Autodesk Fusion 360 part; units mm, degrees
(part 6 of 10)
sketch "Thin nut envelope sketch (13)" plane through (0, 0, 20.6) normal (0, 0, 1) x (1, 0, 0) in component "REFERENCE thin METAL channel nut side 00R Y"
  line L0 (92, 17.8) -> (104, 17.8)
  line L1 (104, 17.8) -> (104, 20.5)
  line L2 (104, 20.5) -> (92, 20.5)
  line L3 (92, 20.5) -> (92, 17.8)
  dimension "d2381" = 92
  dimension "d2382" = 17.8
  dimension "d2383" = 12
  dimension "d2384" = 2.7
  constraint horizontal L0
  constraint vertical L1
  constraint horizontal L2
  constraint vertical L3
  measures "d2381" horizontal distance of origin L0.start
  measures "d2382" vertical distance of origin L0.start
  measures "d2383" horizontal distance of L0.start L0.end
  measures "d2384" vertical distance of L0.end L1.end
extrude "Thin nut envelope''''''''''''" add sketch "Thin nut envelope sketch (13)" along normal blind 8.8 separate body makes body 66 in component "REFERENCE thin METAL channel nut side 00R Y"
ref_plane "WorkPlane2" through (0, 17.8, 0) normal (0, 1, 0) x (0, 0, 1) in component "REFERENCE thin METAL channel nut side 00R Y"
sketch "Thread envelope sketch (13)" plane through (0, 17.8, 0) normal (0, 1, 0) x (1, 0, 0) in component "REFERENCE thin METAL channel nut side 00R Y"
  circle A0 centre (98, -25) radius 2.6
  dimension "d2389" = 98
  dimension "d2390" = 25
  dimension "d2391" = 5.2
  measures "d2389" horizontal distance of origin A0.centre
  measures "d2390" vertical distance of origin A0.centre
  measures "d2391" diameter of A0
extrude "Thread envelope''''''''''''" cut sketch "Thread envelope sketch (13)" along normal blind 2.7 bodies 66 in component "REFERENCE thin METAL channel nut side 00R Y"
ref_plane "WorkPlane1" through (0, 0, 17) normal (0, 0, 1) x (1, 0, 0) in component "METAL in-bay corner 10L"
sketch "Vertical bracket leg sketch (3)" plane through (0, 0, 17) normal (0, 0, 1) x (1, 0, 0) in component "METAL in-bay corner 10L"
  line L0 (130, 22) -> (133, 22)
  line L1 (133, 22) -> (133, 40)
  line L2 (133, 40) -> (130, 40)
  line L3 (130, 40) -> (130, 22)
  dimension "d2396" = 130
  dimension "d2397" = 22
  dimension "d2398" = 3
  dimension "d2399" = 18
  constraint horizontal L0
  constraint vertical L1
  constraint horizontal L2
  constraint vertical L3
  measures "d2396" horizontal distance of origin L0.start
  measures "d2397" vertical distance of origin L0.start
  measures "d2398" horizontal distance of L0.start L0.end
  measures "d2399" vertical distance of L0.end L1.end
extrude "Vertical bracket leg''" add sketch "Vertical bracket leg sketch (3)" along normal blind 16 separate body makes body 67 in component "METAL in-bay corner 10L"
ref_plane "WorkPlane2" through (0, 0, 17) normal (0, 0, 1) x (1, 0, 0) in component "METAL in-bay corner 10L"
sketch "Horizontal bracket leg sketch (3)" plane through (0, 0, 17) normal (0, 0, 1) x (1, 0, 0) in component "METAL in-bay corner 10L"
  line L0 (130, 22) -> (148, 22)
  line L1 (148, 22) -> (148, 25)
  line L2 (148, 25) -> (130, 25)
  line L3 (130, 25) -> (130, 22)
  dimension "d2404" = 130
  dimension "d2405" = 22
  dimension "d2406" = 18
  dimension "d2407" = 3
  constraint horizontal L0
  constraint vertical L1
  constraint horizontal L2
  constraint vertical L3
  measures "d2404" horizontal distance of origin L0.start
  measures "d2405" vertical distance of origin L0.start
  measures "d2406" horizontal distance of L0.start L0.end
  measures "d2407" vertical distance of L0.end L1.end
extrude "Horizontal bracket leg''" add sketch "Horizontal bracket leg sketch (3)" along normal blind 16 bodies 67 in component "METAL in-bay corner 10L"
ref_plane "WorkPlane3" through (130, 0, 0) normal (1, 0, 0) x (0, 1, 0) in component "METAL in-bay corner 10L"
sketch "Vertical rail bolt sketch (3)" plane through (130, 0, 0) normal (1, 0, 0) x (0, 0, -1) in component "METAL in-bay corner 10L"
  circle A0 centre (-25, 34) radius 2.75
  dimension "d2412" = 25
  dimension "d2413" = 34
  dimension "d2414" = 5.5
  measures "d2412" horizontal distance of origin A0.centre
  measures "d2413" vertical distance of origin A0.centre
  measures "d2414" diameter of A0
extrude "Vertical rail bolt''" cut sketch "Vertical rail bolt sketch (3)" along normal blind 3 bodies 67 in component "METAL in-bay corner 10L"
ref_plane "WorkPlane4" through (0, 22, 0) normal (0, 1, 0) x (0, 0, 1) in component "METAL in-bay corner 10L"
sketch "Tie bolt sketch (3)" plane through (0, 22, 0) normal (0, 1, 0) x (1, 0, 0) in component "METAL in-bay corner 10L"
  circle A0 centre (142, -25) radius 2.75
  dimension "d2419" = 142
  dimension "d2420" = 25
  dimension "d2421" = 5.5
  measures "d2419" horizontal distance of origin A0.centre
  measures "d2420" vertical distance of origin A0.centre
  measures "d2421" diameter of A0
extrude "Tie bolt''" cut sketch "Tie bolt sketch (3)" along normal blind 3 bodies 67 in component "METAL in-bay corner 10L"
ref_plane "WorkPlane1" through (133, 0, 0) normal (1, 0, 0) x (0, 1, 0) in component "REFERENCE side M5x8 10L X"
sketch "Button head envelope sketch (14)" plane through (133, 0, 0) normal (1, 0, 0) x (0, 0, -1) in component "REFERENCE side M5x8 10L X"
  circle A0 centre (-25, 34) radius 4.75
  dimension "d2426" = 25
  dimension "d2427" = 34
  dimension "d2428" = 9.5
  measures "d2426" horizontal distance of origin A0.centre
  measures "d2427" vertical distance of origin A0.centre
  measures "d2428" diameter of A0
extrude "Button head envelope'''''''''''''" add sketch "Button head envelope sketch (14)" along normal blind 3 separate body makes body 68 in component "REFERENCE side M5x8 10L X"
ref_plane "WorkPlane2" through (133, 0, 0) normal (1, 0, 0) x (0, 1, 0) in component "REFERENCE side M5x8 10L X"
sketch "Shank envelope sketch (14)" plane through (133, 0, 0) normal (1, 0, 0) x (0, 0, -1) in component "REFERENCE side M5x8 10L X"
  circle A0 centre (-25, 34) radius 2.5
  dimension "d2433" = 25
  dimension "d2434" = 34
  dimension "d2435" = 5
  measures "d2433" horizontal distance of origin A0.centre
  measures "d2434" vertical distance of origin A0.centre
  measures "d2435" diameter of A0
extrude "Shank envelope'''''''''''''" add sketch "Shank envelope sketch (14)" against normal blind 8 bodies 68 in component "REFERENCE side M5x8 10L X"
ref_plane "WorkPlane1" through (0, 0, 20.6) normal (0, 0, 1) x (1, 0, 0) in component "REFERENCE thin METAL channel nut side 10L X"
sketch "Thin nut envelope sketch (14)" plane through (0, 0, 20.6) normal (0, 0, 1) x (1, 0, 0) in component "REFERENCE thin METAL channel nut side 10L X"
  line L0 (125.8, 28) -> (128.5, 28)
  line L1 (128.5, 28) -> (128.5, 40)
  line L2 (128.5, 40) -> (125.8, 40)
  line L3 (125.8, 40) -> (125.8, 28)
  dimension "d2440" = 125.8
  dimension "d2441" = 28
  dimension "d2442" = 2.7
  dimension "d2443" = 12
  constraint horizontal L0
  constraint vertical L1
  constraint horizontal L2
  constraint vertical L3
  measures "d2440" horizontal distance of origin L0.start
  measures "d2441" vertical distance of origin L0.start
  measures "d2442" horizontal distance of L0.start L0.end
  measures "d2443" vertical distance of L0.end L1.end
extrude "Thin nut envelope'''''''''''''" add sketch "Thin nut envelope sketch (14)" along normal blind 8.8 separate body makes body 69 in component "REFERENCE thin METAL channel nut side 10L X"
ref_plane "WorkPlane2" through (125.8, 0, 0) normal (1, 0, 0) x (0, 1, 0) in component "REFERENCE thin METAL channel nut side 10L X"
sketch "Thread envelope sketch (14)" plane through (125.8, 0, 0) normal (1, 0, 0) x (0, 0, -1) in component "REFERENCE thin METAL channel nut side 10L X"
  circle A0 centre (-25, 34) radius 2.6
  dimension "d2448" = 25
  dimension "d2449" = 34
  dimension "d2450" = 5.2
  measures "d2448" horizontal distance of origin A0.centre
  measures "d2449" vertical distance of origin A0.centre
  measures "d2450" diameter of A0
extrude "Thread envelope'''''''''''''" cut sketch "Thread envelope sketch (14)" along normal blind 2.7 bodies 69 in component "REFERENCE thin METAL channel nut side 10L X"
ref_plane "WorkPlane1" through (0, 25, 0) normal (0, 1, 0) x (0, 0, 1) in component "REFERENCE side M5x8 10L Y"
sketch "Button head envelope sketch (15)" plane through (0, 25, 0) normal (0, 1, 0) x (1, 0, 0) in component "REFERENCE side M5x8 10L Y"
  circle A0 centre (142, -25) radius 4.75
  dimension "d2455" = 142
  dimension "d2456" = 25
  dimension "d2457" = 9.5
  measures "d2455" horizontal distance of origin A0.centre
  measures "d2456" vertical distance of origin A0.centre
  measures "d2457" diameter of A0
extrude "Button head envelope''''''''''''''" add sketch "Button head envelope sketch (15)" along normal blind 3 separate body makes body 70 in component "REFERENCE side M5x8 10L Y"
ref_plane "WorkPlane2" through (0, 25, 0) normal (0, 1, 0) x (0, 0, 1) in component "REFERENCE side M5x8 10L Y"
sketch "Shank envelope sketch (15)" plane through (0, 25, 0) normal (0, 1, 0) x (1, 0, 0) in component "REFERENCE side M5x8 10L Y"
  circle A0 centre (142, -25) radius 2.5
  dimension "d2462" = 142
  dimension "d2463" = 25
  dimension "d2464" = 5
  measures "d2462" horizontal distance of origin A0.centre
  measures "d2463" vertical distance of origin A0.centre
  measures "d2464" diameter of A0
extrude "Shank envelope''''''''''''''" add sketch "Shank envelope sketch (15)" against normal blind 8 bodies 70 in component "REFERENCE side M5x8 10L Y"
ref_plane "WorkPlane1" through (0, 0, 20.6) normal (0, 0, 1) x (1, 0, 0) in component "REFERENCE thin METAL channel nut side 10L Y"
sketch "Thin nut envelope sketch (15)" plane through (0, 0, 20.6) normal (0, 0, 1) x (1, 0, 0) in component "REFERENCE thin METAL channel nut side 10L Y"
  line L0 (136, 17.8) -> (148, 17.8)
  line L1 (148, 17.8) -> (148, 20.5)
  line L2 (148, 20.5) -> (136, 20.5)
  line L3 (136, 20.5) -> (136, 17.8)
  dimension "d2469" = 136
  dimension "d2470" = 17.8
  dimension "d2471" = 12
  dimension "d2472" = 2.7
  constraint horizontal L0
  constraint vertical L1
  constraint horizontal L2
  constraint vertical L3
  measures "d2469" horizontal distance of origin L0.start
  measures "d2470" vertical distance of origin L0.start
  measures "d2471" horizontal distance of L0.start L0.end
  measures "d2472" vertical distance of L0.end L1.end
extrude "Thin nut envelope''''''''''''''" add sketch "Thin nut envelope sketch (15)" along normal blind 8.8 separate body makes body 71 in component "REFERENCE thin METAL channel nut side 10L Y"
ref_plane "WorkPlane2" through (0, 17.8, 0) normal (0, 1, 0) x (0, 0, 1) in component "REFERENCE thin METAL channel nut side 10L Y"
sketch "Thread envelope sketch (15)" plane through (0, 17.8, 0) normal (0, 1, 0) x (1, 0, 0) in component "REFERENCE thin METAL channel nut side 10L Y"
  circle A0 centre (142, -25) radius 2.6
  dimension "d2477" = 142
  dimension "d2478" = 25
  dimension "d2479" = 5.2
  measures "d2477" horizontal distance of origin A0.centre
  measures "d2478" vertical distance of origin A0.centre
  measures "d2479" diameter of A0
extrude "Thread envelope''''''''''''''" cut sketch "Thread envelope sketch (15)" along normal blind 2.7 bodies 71 in component "REFERENCE thin METAL channel nut side 10L Y"
ref_plane "WorkPlane1" through (0, 0, 17) normal (0, 0, 1) x (1, 0, 0) in component "METAL in-bay corner 10R"
sketch "Vertical bracket leg sketch (4)" plane through (0, 0, 17) normal (0, 0, 1) x (1, 0, 0) in component "METAL in-bay corner 10R"
  line L0 (215, 22) -> (218, 22)
  line L1 (218, 22) -> (218, 40)
  line L2 (218, 40) -> (215, 40)
  line L3 (215, 40) -> (215, 22)
  dimension "d2484" = 215
  dimension "d2485" = 22
  dimension "d2486" = 3
  dimension "d2487" = 18
  constraint horizontal L0
  constraint vertical L1
  constraint horizontal L2
  constraint vertical L3
  measures "d2484" horizontal distance of origin L0.start
  measures "d2485" vertical distance of origin L0.start
  measures "d2486" horizontal distance of L0.start L0.end
  measures "d2487" vertical distance of L0.end L1.end
extrude "Vertical bracket leg'''" add sketch "Vertical bracket leg sketch (4)" along normal blind 16 separate body makes body 72 in component "METAL in-bay corner 10R"
ref_plane "WorkPlane2" through (0, 0, 17) normal (0, 0, 1) x (1, 0, 0) in component "METAL in-bay corner 10R"
sketch "Horizontal bracket leg sketch (4)" plane through (0, 0, 17) normal (0, 0, 1) x (1, 0, 0) in component "METAL in-bay corner 10R"
  line L0 (200, 22) -> (218, 22)
  line L1 (218, 22) -> (218, 25)
  line L2 (218, 25) -> (200, 25)
  line L3 (200, 25) -> (200, 22)
  dimension "d2492" = 200
  dimension "d2493" = 22
  dimension "d2494" = 18
  dimension "d2495" = 3
  constraint horizontal L0
  constraint vertical L1
  constraint horizontal L2
  constraint vertical L3
  measures "d2492" horizontal distance of origin L0.start
  measures "d2493" vertical distance of origin L0.start
  measures "d2494" horizontal distance of L0.start L0.end
  measures "d2495" vertical distance of L0.end L1.end
extrude "Horizontal bracket leg'''" add sketch "Horizontal bracket leg sketch (4)" along normal blind 16 bodies 72 in component "METAL in-bay corner 10R"
ref_plane "WorkPlane3" through (218, 0, 0) normal (1, 0, 0) x (0, 1, 0) in component "METAL in-bay corner 10R"
sketch "Vertical rail bolt sketch (4)" plane through (218, 0, 0) normal (1, 0, 0) x (0, 0, -1) in component "METAL in-bay corner 10R"
  circle A0 centre (-25, 34) radius 2.75
  dimension "d2500" = 25
  dimension "d2501" = 34
  dimension "d2502" = 5.5
  measures "d2500" horizontal distance of origin A0.centre
  measures "d2501" vertical distance of origin A0.centre
  measures "d2502" diameter of A0
extrude "Vertical rail bolt'''" cut sketch "Vertical rail bolt sketch (4)" against normal blind 3 bodies 72 in component "METAL in-bay corner 10R"
ref_plane "WorkPlane4" through (0, 22, 0) normal (0, 1, 0) x (0, 0, 1) in component "METAL in-bay corner 10R"
sketch "Tie bolt sketch (4)" plane through (0, 22, 0) normal (0, 1, 0) x (1, 0, 0) in component "METAL in-bay corner 10R"
  circle A0 centre (206, -25) radius 2.75
  dimension "d2507" = 206
  dimension "d2508" = 25
  dimension "d2509" = 5.5
  measures "d2507" horizontal distance of origin A0.centre
  measures "d2508" vertical distance of origin A0.centre
  measures "d2509" diameter of A0
extrude "Tie bolt'''" cut sketch "Tie bolt sketch (4)" along normal blind 3 bodies 72 in component "METAL in-bay corner 10R"
ref_plane "WorkPlane1" through (215, 0, 0) normal (1, 0, 0) x (0, 1, 0) in component "REFERENCE side M5x8 10R X"
sketch "Button head envelope sketch (16)" plane through (215, 0, 0) normal (1, 0, 0) x (0, 0, -1) in component "REFERENCE side M5x8 10R X"
  circle A0 centre (-25, 34) radius 4.75
  dimension "d2514" = 25
  dimension "d2515" = 34
  dimension "d2516" = 9.5
  measures "d2514" horizontal distance of origin A0.centre
  measures "d2515" vertical distance of origin A0.centre
  measures "d2516" diameter of A0
extrude "Button head envelope'''''''''''''''" add sketch "Button head envelope sketch (16)" against normal blind 3 separate body makes body 73 in component "REFERENCE side M5x8 10R X"
ref_plane "WorkPlane2" through (215, 0, 0) normal (1, 0, 0) x (0, 1, 0) in component "REFERENCE side M5x8 10R X"
sketch "Shank envelope sketch (16)" plane through (215, 0, 0) normal (1, 0, 0) x (0, 0, -1) in component "REFERENCE side M5x8 10R X"
  circle A0 centre (-25, 34) radius 2.5
  dimension "d2521" = 25
  dimension "d2522" = 34
  dimension "d2523" = 5
  measures "d2521" horizontal distance of origin A0.centre
  measures "d2522" vertical distance of origin A0.centre
  measures "d2523" diameter of A0
extrude "Shank envelope'''''''''''''''" add sketch "Shank envelope sketch (16)" along normal blind 8 bodies 73 in component "REFERENCE side M5x8 10R X"
ref_plane "WorkPlane1" through (0, 0, 20.6) normal (0, 0, 1) x (1, 0, 0) in component "REFERENCE thin METAL channel nut side 10R X"
sketch "Thin nut envelope sketch (16)" plane through (0, 0, 20.6) normal (0, 0, 1) x (1, 0, 0) in component "REFERENCE thin METAL channel nut side 10R X"
  line L0 (219.5, 28) -> (222.2, 28)
  line L1 (222.2, 28) -> (222.2, 40)
  line L2 (222.2, 40) -> (219.5, 40)
  line L3 (219.5, 40) -> (219.5, 28)
  dimension "d2528" = 219.5
  dimension "d2529" = 28
  dimension "d2530" = 2.7
  dimension "d2531" = 12
  constraint horizontal L0
  constraint vertical L1
  constraint horizontal L2
  constraint vertical L3
  measures "d2528" horizontal distance of origin L0.start
  measures "d2529" vertical distance of origin L0.start
  measures "d2530" horizontal distance of L0.start L0.end
  measures "d2531" vertical distance of L0.end L1.end
extrude "Thin nut envelope'''''''''''''''" add sketch "Thin nut envelope sketch (16)" along normal blind 8.8 separate body makes body 74 in component "REFERENCE thin METAL channel nut side 10R X"
ref_plane "WorkPlane2" through (219.5, 0, 0) normal (1, 0, 0) x (0, 1, 0) in component "REFERENCE thin METAL channel nut side 10R X"
sketch "Thread envelope sketch (16)" plane through (219.5, 0, 0) normal (1, 0, 0) x (0, 0, -1) in component "REFERENCE thin METAL channel nut side 10R X"
  circle A0 centre (-25, 34) radius 2.6
  dimension "d2536" = 25
  dimension "d2537" = 34
  dimension "d2538" = 5.2
  measures "d2536" horizontal distance of origin A0.centre
  measures "d2537" vertical distance of origin A0.centre
  measures "d2538" diameter of A0
extrude "Thread envelope'''''''''''''''" cut sketch "Thread envelope sketch (16)" along normal blind 2.7 bodies 74 in component "REFERENCE thin METAL channel nut side 10R X"
ref_plane "WorkPlane1" through (0, 25, 0) normal (0, 1, 0) x (0, 0, 1) in component "REFERENCE side M5x8 10R Y"
sketch "Button head envelope sketch (17)" plane through (0, 25, 0) normal (0, 1, 0) x (1, 0, 0) in component "REFERENCE side M5x8 10R Y"
  circle A0 centre (206, -25) radius 4.75
  dimension "d2543" = 206
  dimension "d2544" = 25
  dimension "d2545" = 9.5
  measures "d2543" horizontal distance of origin A0.centre
  measures "d2544" vertical distance of origin A0.centre
  measures "d2545" diameter of A0
extrude "Button head envelope''''''''''''''''" add sketch "Button head envelope sketch (17)" along normal blind 3 separate body makes body 75 in component "REFERENCE side M5x8 10R Y"
ref_plane "WorkPlane2" through (0, 25, 0) normal (0, 1, 0) x (0, 0, 1) in component "REFERENCE side M5x8 10R Y"
sketch "Shank envelope sketch (17)" plane through (0, 25, 0) normal (0, 1, 0) x (1, 0, 0) in component "REFERENCE side M5x8 10R Y"
  circle A0 centre (206, -25) radius 2.5
  dimension "d2550" = 206
  dimension "d2551" = 25
  dimension "d2552" = 5
  measures "d2550" horizontal distance of origin A0.centre
  measures "d2551" vertical distance of origin A0.centre
  measures "d2552" diameter of A0
extrude "Shank envelope''''''''''''''''" add sketch "Shank envelope sketch (17)" against normal blind 8 bodies 75 in component "REFERENCE side M5x8 10R Y"
ref_plane "WorkPlane1" through (0, 0, 20.6) normal (0, 0, 1) x (1, 0, 0) in component "REFERENCE thin METAL channel nut side 10R Y"
sketch "Thin nut envelope sketch (17)" plane through (0, 0, 20.6) normal (0, 0, 1) x (1, 0, 0) in component "REFERENCE thin METAL channel nut side 10R Y"
  line L0 (200, 17.8) -> (212, 17.8)
  line L1 (212, 17.8) -> (212, 20.5)
  line L2 (212, 20.5) -> (200, 20.5)
  line L3 (200, 20.5) -> (200, 17.8)
  dimension "d2557" = 200
  dimension "d2558" = 17.8
  dimension "d2559" = 12
  dimension "d2560" = 2.7
  constraint horizontal L0
  constraint vertical L1
  constraint horizontal L2
  constraint vertical L3
  measures "d2557" horizontal distance of origin L0.start
  measures "d2558" vertical distance of origin L0.start
  measures "d2559" horizontal distance of L0.start L0.end
  measures "d2560" vertical distance of L0.end L1.end
extrude "Thin nut envelope''''''''''''''''" add sketch "Thin nut envelope sketch (17)" along normal blind 8.8 separate body makes body 76 in component "REFERENCE thin METAL channel nut side 10R Y"
ref_plane "WorkPlane2" through (0, 17.8, 0) normal (0, 1, 0) x (0, 0, 1) in component "REFERENCE thin METAL channel nut side 10R Y"
sketch "Thread envelope sketch (17)" plane through (0, 17.8, 0) normal (0, 1, 0) x (1, 0, 0) in component "REFERENCE thin METAL channel nut side 10R Y"
  circle A0 centre (206, -25) radius 2.6
  dimension "d2565" = 206
  dimension "d2566" = 25
  dimension "d2567" = 5.2
  measures "d2565" horizontal distance of origin A0.centre
  measures "d2566" vertical distance of origin A0.centre
  measures "d2567" diameter of A0
extrude "Thread envelope''''''''''''''''" cut sketch "Thread envelope sketch (17)" along normal blind 2.7 bodies 76 in component "REFERENCE thin METAL channel nut side 10R Y"
ref_plane "WorkPlane1" through (0, 0, 17) normal (0, 0, 1) x (1, 0, 0) in component "METAL in-bay corner 01L"
sketch "Vertical bracket leg sketch (5)" plane through (0, 0, 17) normal (0, 0, 1) x (1, 0, 0) in component "METAL in-bay corner 01L"
  line L0 (22, 200) -> (25, 200)
  line L1 (25, 200) -> (25, 218)
  line L2 (25, 218) -> (22, 218)
  line L3 (22, 218) -> (22, 200)
  dimension "d2572" = 22
  dimension "d2573" = 200
  dimension "d2574" = 3
  dimension "d2575" = 18
  constraint horizontal L0
  constraint vertical L1
  constraint horizontal L2
  constraint vertical L3
  measures "d2572" horizontal distance of origin L0.start
  measures "d2573" vertical distance of origin L0.start
  measures "d2574" horizontal distance of L0.start L0.end
  measures "d2575" vertical distance of L0.end L1.end
extrude "Vertical bracket leg''''" add sketch "Vertical bracket leg sketch (5)" along normal blind 16 separate body makes body 77 in component "METAL in-bay corner 01L"
ref_plane "WorkPlane2" through (0, 0, 17) normal (0, 0, 1) x (1, 0, 0) in component "METAL in-bay corner 01L"
sketch "Horizontal bracket leg sketch (5)" plane through (0, 0, 17) normal (0, 0, 1) x (1, 0, 0) in component "METAL in-bay corner 01L"
  line L0 (22, 215) -> (40, 215)
  line L1 (40, 215) -> (40, 218)
  line L2 (40, 218) -> (22, 218)
  line L3 (22, 218) -> (22, 215)
  dimension "d2580" = 22
  dimension "d2581" = 215
  dimension "d2582" = 18
  dimension "d2583" = 3
  constraint horizontal L0
  constraint vertical L1
  constraint horizontal L2
  constraint vertical L3
  measures "d2580" horizontal distance of origin L0.start
  measures "d2581" vertical distance of origin L0.start
  measures "d2582" horizontal distance of L0.start L0.end
  measures "d2583" vertical distance of L0.end L1.end
extrude "Horizontal bracket leg''''" add sketch "Horizontal bracket leg sketch (5)" along normal blind 16 bodies 77 in component "METAL in-bay corner 01L"
ref_plane "WorkPlane3" through (22, 0, 0) normal (1, 0, 0) x (0, 1, 0) in component "METAL in-bay corner 01L"
sketch "Vertical rail bolt sketch (5)" plane through (22, 0, 0) normal (1, 0, 0) x (0, 0, -1) in component "METAL in-bay corner 01L"
  circle A0 centre (-25, 206) radius 2.75
  dimension "d2588" = 25
  dimension "d2589" = 206
  dimension "d2590" = 5.5
  measures "d2588" horizontal distance of origin A0.centre
  measures "d2589" vertical distance of origin A0.centre
  measures "d2590" diameter of A0
extrude "Vertical rail bolt''''" cut sketch "Vertical rail bolt sketch (5)" along normal blind 3 bodies 77 in component "METAL in-bay corner 01L"
ref_plane "WorkPlane4" through (0, 218, 0) normal (0, 1, 0) x (0, 0, 1) in component "METAL in-bay corner 01L"
sketch "Tie bolt sketch (5)" plane through (0, 218, 0) normal (0, 1, 0) x (1, 0, 0) in component "METAL in-bay corner 01L"
  circle A0 centre (34, -25) radius 2.75
  dimension "d2595" = 34
  dimension "d2596" = 25
  dimension "d2597" = 5.5
  measures "d2595" horizontal distance of origin A0.centre
  measures "d2596" vertical distance of origin A0.centre
  measures "d2597" diameter of A0
extrude "Tie bolt''''" cut sketch "Tie bolt sketch (5)" against normal blind 3 bodies 77 in component "METAL in-bay corner 01L"
ref_plane "WorkPlane1" through (25, 0, 0) normal (1, 0, 0) x (0, 1, 0) in component "REFERENCE side M5x8 01L X"
sketch "Button head envelope sketch (18)" plane through (25, 0, 0) normal (1, 0, 0) x (0, 0, -1) in component "REFERENCE side M5x8 01L X"
  circle A0 centre (-25, 206) radius 4.75
  dimension "d2602" = 25
  dimension "d2603" = 206
  dimension "d2604" = 9.5
  measures "d2602" horizontal distance of origin A0.centre
  measures "d2603" vertical distance of origin A0.centre
  measures "d2604" diameter of A0
extrude "Button head envelope'''''''''''''''''" add sketch "Button head envelope sketch (18)" along normal blind 3 separate body makes body 78 in component "REFERENCE side M5x8 01L X"
ref_plane "WorkPlane2" through (25, 0, 0) normal (1, 0, 0) x (0, 1, 0) in component "REFERENCE side M5x8 01L X"
sketch "Shank envelope sketch (18)" plane through (25, 0, 0) normal (1, 0, 0) x (0, 0, -1) in component "REFERENCE side M5x8 01L X"
  circle A0 centre (-25, 206) radius 2.5
  dimension "d2609" = 25
  dimension "d2610" = 206
  dimension "d2611" = 5
  measures "d2609" horizontal distance of origin A0.centre
  measures "d2610" vertical distance of origin A0.centre
  measures "d2611" diameter of A0
extrude "Shank envelope'''''''''''''''''" add sketch "Shank envelope sketch (18)" against normal blind 8 bodies 78 in component "REFERENCE side M5x8 01L X"
ref_plane "WorkPlane1" through (0, 0, 20.6) normal (0, 0, 1) x (1, 0, 0) in component "REFERENCE thin METAL channel nut side 01L X"
sketch "Thin nut envelope sketch (18)" plane through (0, 0, 20.6) normal (0, 0, 1) x (1, 0, 0) in component "REFERENCE thin METAL channel nut side 01L X"
  line L0 (17.8, 200) -> (20.5, 200)
  line L1 (20.5, 200) -> (20.5, 212)
  line L2 (20.5, 212) -> (17.8, 212)
  line L3 (17.8, 212) -> (17.8, 200)
  dimension "d2616" = 17.8
  dimension "d2617" = 200
  dimension "d2618" = 2.7
  dimension "d2619" = 12
  constraint horizontal L0
  constraint vertical L1
  constraint horizontal L2
  constraint vertical L3
  measures "d2616" horizontal distance of origin L0.start
  measures "d2617" vertical distance of origin L0.start
  measures "d2618" horizontal distance of L0.start L0.end
  measures "d2619" vertical distance of L0.end L1.end
extrude "Thin nut envelope'''''''''''''''''" add sketch "Thin nut envelope sketch (18)" along normal blind 8.8 separate body makes body 79 in component "REFERENCE thin METAL channel nut side 01L X"
ref_plane "WorkPlane2" through (17.8, 0, 0) normal (1, 0, 0) x (0, 1, 0) in component "REFERENCE thin METAL channel nut side 01L X"
sketch "Thread envelope sketch (18)" plane through (17.8, 0, 0) normal (1, 0, 0) x (0, 0, -1) in component "REFERENCE thin METAL channel nut side 01L X"
  circle A0 centre (-25, 206) radius 2.6
  dimension "d2624" = 25
  dimension "d2625" = 206
  dimension "d2626" = 5.2
  measures "d2624" horizontal distance of origin A0.centre
  measures "d2625" vertical distance of origin A0.centre
  measures "d2626" diameter of A0
extrude "Thread envelope'''''''''''''''''" cut sketch "Thread envelope sketch (18)" along normal blind 2.7 bodies 79 in component "REFERENCE thin METAL channel nut side 01L X"
ref_plane "WorkPlane1" through (0, 215, 0) normal (0, 1, 0) x (0, 0, 1) in component "REFERENCE side M5x8 01L Y"
sketch "Button head envelope sketch (19)" plane through (0, 215, 0) normal (0, 1, 0) x (1, 0, 0) in component "REFERENCE side M5x8 01L Y"
  circle A0 centre (34, -25) radius 4.75
  dimension "d2631" = 34
  dimension "d2632" = 25
  dimension "d2633" = 9.5
  measures "d2631" horizontal distance of origin A0.centre
  measures "d2632" vertical distance of origin A0.centre
  measures "d2633" diameter of A0
extrude "Button head envelope''''''''''''''''''" add sketch "Button head envelope sketch (19)" against normal blind 3 separate body makes body 80 in component "REFERENCE side M5x8 01L Y"
ref_plane "WorkPlane2" through (0, 215, 0) normal (0, 1, 0) x (0, 0, 1) in component "REFERENCE side M5x8 01L Y"
sketch "Shank envelope sketch (19)" plane through (0, 215, 0) normal (0, 1, 0) x (1, 0, 0) in component "REFERENCE side M5x8 01L Y"
  circle A0 centre (34, -25) radius 2.5
  dimension "d2638" = 34
  dimension "d2639" = 25
  dimension "d2640" = 5
  measures "d2638" horizontal distance of origin A0.centre
  measures "d2639" vertical distance of origin A0.centre
  measures "d2640" diameter of A0
extrude "Shank envelope''''''''''''''''''" add sketch "Shank envelope sketch (19)" along normal blind 8 bodies 80 in component "REFERENCE side M5x8 01L Y"
ref_plane "WorkPlane1" through (0, 0, 20.6) normal (0, 0, 1) x (1, 0, 0) in component "REFERENCE thin METAL channel nut side 01L Y"
sketch "Thin nut envelope sketch (19)" plane through (0, 0, 20.6) normal (0, 0, 1) x (1, 0, 0) in component "REFERENCE thin METAL channel nut side 01L Y"
  line L0 (28, 219.5) -> (40, 219.5)
  line L1 (40, 219.5) -> (40, 222.2)
  line L2 (40, 222.2) -> (28, 222.2)
  line L3 (28, 222.2) -> (28, 219.5)
  dimension "d2645" = 28
  dimension "d2646" = 219.5
  dimension "d2647" = 12
  dimension "d2648" = 2.7
  constraint horizontal L0
  constraint vertical L1
  constraint horizontal L2
  constraint vertical L3
  measures "d2645" horizontal distance of origin L0.start
  measures "d2646" vertical distance of origin L0.start
  measures "d2647" horizontal distance of L0.start L0.end
  measures "d2648" vertical distance of L0.end L1.end
extrude "Thin nut envelope''''''''''''''''''" add sketch "Thin nut envelope sketch (19)" along normal blind 8.8 separate body makes body 81 in component "REFERENCE thin METAL channel nut side 01L Y"
ref_plane "WorkPlane2" through (0, 219.5, 0) normal (0, 1, 0) x (0, 0, 1) in component "REFERENCE thin METAL channel nut side 01L Y"
sketch "Thread envelope sketch (19)" plane through (0, 219.5, 0) normal (0, 1, 0) x (1, 0, 0) in component "REFERENCE thin METAL channel nut side 01L Y"
  circle A0 centre (34, -25) radius 2.6
  dimension "d2653" = 34
  dimension "d2654" = 25
  dimension "d2655" = 5.2
  measures "d2653" horizontal distance of origin A0.centre
  measures "d2654" vertical distance of origin A0.centre
  measures "d2655" diameter of A0
extrude "Thread envelope''''''''''''''''''" cut sketch "Thread envelope sketch (19)" along normal blind 2.7 bodies 81 in component "REFERENCE thin METAL channel nut side 01L Y"
ref_plane "WorkPlane1" through (0, 0, 17) normal (0, 0, 1) x (1, 0, 0) in component "METAL in-bay corner 01R"
sketch "Vertical bracket leg sketch (6)" plane through (0, 0, 17) normal (0, 0, 1) x (1, 0, 0) in component "METAL in-bay corner 01R"
  line L0 (107, 200) -> (110, 200)
  line L1 (110, 200) -> (110, 218)
  line L2 (110, 218) -> (107, 218)
  line L3 (107, 218) -> (107, 200)
  dimension "d2660" = 107
  dimension "d2661" = 200
  dimension "d2662" = 3
  dimension "d2663" = 18
  constraint horizontal L0
  constraint vertical L1
  constraint horizontal L2
  constraint vertical L3
  measures "d2660" horizontal distance of origin L0.start
  measures "d2661" vertical distance of origin L0.start
  measures "d2662" horizontal distance of L0.start L0.end
  measures "d2663" vertical distance of L0.end L1.end
extrude "Vertical bracket leg'''''" add sketch "Vertical bracket leg sketch (6)" along normal blind 16 separate body makes body 82 in component "METAL in-bay corner 01R"
ref_plane "WorkPlane2" through (0, 0, 17) normal (0, 0, 1) x (1, 0, 0) in component "METAL in-bay corner 01R"
sketch "Horizontal bracket leg sketch (6)" plane through (0, 0, 17) normal (0, 0, 1) x (1, 0, 0) in component "METAL in-bay corner 01R"
  line L0 (92, 215) -> (110, 215)
  line L1 (110, 215) -> (110, 218)
  line L2 (110, 218) -> (92, 218)
  line L3 (92, 218) -> (92, 215)
  dimension "d2668" = 92
  dimension "d2669" = 215
  dimension "d2670" = 18
  dimension "d2671" = 3
  constraint horizontal L0
  constraint vertical L1
  constraint horizontal L2
  constraint vertical L3
  measures "d2668" horizontal distance of origin L0.start
  measures "d2669" vertical distance of origin L0.start
  measures "d2670" horizontal distance of L0.start L0.end
  measures "d2671" vertical distance of L0.end L1.end
extrude "Horizontal bracket leg'''''" add sketch "Horizontal bracket leg sketch (6)" along normal blind 16 bodies 82 in component "METAL in-bay corner 01R"
ref_plane "WorkPlane3" through (110, 0, 0) normal (1, 0, 0) x (0, 1, 0) in component "METAL in-bay corner 01R"
sketch "Vertical rail bolt sketch (6)" plane through (110, 0, 0) normal (1, 0, 0) x (0, 0, -1) in component "METAL in-bay corner 01R"
  circle A0 centre (-25, 206) radius 2.75
  dimension "d2676" = 25
  dimension "d2677" = 206
  dimension "d2678" = 5.5
  measures "d2676" horizontal distance of origin A0.centre
  measures "d2677" vertical distance of origin A0.centre
  measures "d2678" diameter of A0
extrude "Vertical rail bolt'''''" cut sketch "Vertical rail bolt sketch (6)" against normal blind 3 bodies 82 in component "METAL in-bay corner 01R"
ref_plane "WorkPlane4" through (0, 218, 0) normal (0, 1, 0) x (0, 0, 1) in component "METAL in-bay corner 01R"
sketch "Tie bolt sketch (6)" plane through (0, 218, 0) normal (0, 1, 0) x (1, 0, 0) in component "METAL in-bay corner 01R"
  circle A0 centre (98, -25) radius 2.75
  dimension "d2683" = 98
  dimension "d2684" = 25
  dimension "d2685" = 5.5
  measures "d2683" horizontal distance of origin A0.centre
  measures "d2684" vertical distance of origin A0.centre
  measures "d2685" diameter of A0
extrude "Tie bolt'''''" cut sketch "Tie bolt sketch (6)" against normal blind 3 bodies 82 in component "METAL in-bay corner 01R"
ref_plane "WorkPlane1" through (107, 0, 0) normal (1, 0, 0) x (0, 1, 0) in component "REFERENCE side M5x8 01R X"
sketch "Button head envelope sketch (20)" plane through (107, 0, 0) normal (1, 0, 0) x (0, 0, -1) in component "REFERENCE side M5x8 01R X"
  circle A0 centre (-25, 206) radius 4.75
  dimension "d2690" = 25
  dimension "d2691" = 206
  dimension "d2692" = 9.5
  measures "d2690" horizontal distance of origin A0.centre
  measures "d2691" vertical distance of origin A0.centre
  measures "d2692" diameter of A0
extrude "Button head envelope'''''''''''''''''''" add sketch "Button head envelope sketch (20)" against normal blind 3 separate body makes body 83 in component "REFERENCE side M5x8 01R X"
ref_plane "WorkPlane2" through (107, 0, 0) normal (1, 0, 0) x (0, 1, 0) in component "REFERENCE side M5x8 01R X"
sketch "Shank envelope sketch (20)" plane through (107, 0, 0) normal (1, 0, 0) x (0, 0, -1) in component "REFERENCE side M5x8 01R X"
  circle A0 centre (-25, 206) radius 2.5
  dimension "d2697" = 25
  dimension "d2698" = 206
  dimension "d2699" = 5
  measures "d2697" horizontal distance of origin A0.centre
  measures "d2698" vertical distance of origin A0.centre
  measures "d2699" diameter of A0
extrude "Shank envelope'''''''''''''''''''" add sketch "Shank envelope sketch (20)" along normal blind 8 bodies 83 in component "REFERENCE side M5x8 01R X"
ref_plane "WorkPlane1" through (0, 0, 20.6) normal (0, 0, 1) x (1, 0, 0) in component "REFERENCE thin METAL channel nut side 01R X"
sketch "Thin nut envelope sketch (20)" plane through (0, 0, 20.6) normal (0, 0, 1) x (1, 0, 0) in component "REFERENCE thin METAL channel nut side 01R X"
  line L0 (111.5, 200) -> (114.2, 200)
  line L1 (114.2, 200) -> (114.2, 212)
  line L2 (114.2, 212) -> (111.5, 212)
  line L3 (111.5, 212) -> (111.5, 200)
  dimension "d2704" = 111.5
  dimension "d2705" = 200
  dimension "d2706" = 2.7
  dimension "d2707" = 12
  constraint horizontal L0
  constraint vertical L1
  constraint horizontal L2
  constraint vertical L3
  measures "d2704" horizontal distance of origin L0.start
  measures "d2705" vertical distance of origin L0.start
  measures "d2706" horizontal distance of L0.start L0.end
  measures "d2707" vertical distance of L0.end L1.end
extrude "Thin nut envelope'''''''''''''''''''" add sketch "Thin nut envelope sketch (20)" along normal blind 8.8 separate body makes body 84 in component "REFERENCE thin METAL channel nut side 01R X"
ref_plane "WorkPlane2" through (111.5, 0, 0) normal (1, 0, 0) x (0, 1, 0) in component "REFERENCE thin METAL channel nut side 01R X"
sketch "Thread envelope sketch (20)" plane through (111.5, 0, 0) normal (1, 0, 0) x (0, 0, -1) in component "REFERENCE thin METAL channel nut side 01R X"
  circle A0 centre (-25, 206) radius 2.6
  dimension "d2712" = 25
  dimension "d2713" = 206
  dimension "d2714" = 5.2
  measures "d2712" horizontal distance of origin A0.centre
  measures "d2713" vertical distance of origin A0.centre
  measures "d2714" diameter of A0
extrude "Thread envelope'''''''''''''''''''" cut sketch "Thread envelope sketch (20)" along normal blind 2.7 bodies 84 in component "REFERENCE thin METAL channel nut side 01R X"
ref_plane "WorkPlane1" through (0, 215, 0) normal (0, 1, 0) x (0, 0, 1) in component "REFERENCE side M5x8 01R Y"
sketch "Button head envelope sketch (21)" plane through (0, 215, 0) normal (0, 1, 0) x (1, 0, 0) in component "REFERENCE side M5x8 01R Y"
  circle A0 centre (98, -25) radius 4.75
  dimension "d2719" = 98
  dimension "d2720" = 25
  dimension "d2721" = 9.5
  measures "d2719" horizontal distance of origin A0.centre
  measures "d2720" vertical distance of origin A0.centre
  measures "d2721" diameter of A0
extrude "Button head envelope''''''''''''''''''''" add sketch "Button head envelope sketch (21)" against normal blind 3 separate body makes body 85 in component "REFERENCE side M5x8 01R Y"
ref_plane "WorkPlane2" through (0, 215, 0) normal (0, 1, 0) x (0, 0, 1) in component "REFERENCE side M5x8 01R Y"
sketch "Shank envelope sketch (21)" plane through (0, 215, 0) normal (0, 1, 0) x (1, 0, 0) in component "REFERENCE side M5x8 01R Y"
  circle A0 centre (98, -25) radius 2.5
  dimension "d2726" = 98
  dimension "d2727" = 25
  dimension "d2728" = 5
  measures "d2726" horizontal distance of origin A0.centre
  measures "d2727" vertical distance of origin A0.centre
  measures "d2728" diameter of A0
extrude "Shank envelope''''''''''''''''''''" add sketch "Shank envelope sketch (21)" along normal blind 8 bodies 85 in component "REFERENCE side M5x8 01R Y"
ref_plane "WorkPlane1" through (0, 0, 20.6) normal (0, 0, 1) x (1, 0, 0) in component "REFERENCE thin METAL channel nut side 01R Y"
sketch "Thin nut envelope sketch (21)" plane through (0, 0, 20.6) normal (0, 0, 1) x (1, 0, 0) in component "REFERENCE thin METAL channel nut side 01R Y"
  line L0 (92, 219.5) -> (104, 219.5)
  line L1 (104, 219.5) -> (104, 222.2)
  line L2 (104, 222.2) -> (92, 222.2)
  line L3 (92, 222.2) -> (92, 219.5)
  dimension "d2733" = 92
  dimension "d2734" = 219.5
  dimension "d2735" = 12
  dimension "d2736" = 2.7
  constraint horizontal L0
  constraint vertical L1
  constraint horizontal L2
  constraint vertical L3
  measures "d2733" horizontal distance of origin L0.start
  measures "d2734" vertical distance of origin L0.start
  measures "d2735" horizontal distance of L0.start L0.end
  measures "d2736" vertical distance of L0.end L1.end
extrude "Thin nut envelope''''''''''''''''''''" add sketch "Thin nut envelope sketch (21)" along normal blind 8.8 separate body makes body 86 in component "REFERENCE thin METAL channel nut side 01R Y"
ref_plane "WorkPlane2" through (0, 219.5, 0) normal (0, 1, 0) x (0, 0, 1) in component "REFERENCE thin METAL channel nut side 01R Y"
sketch "Thread envelope sketch (21)" plane through (0, 219.5, 0) normal (0, 1, 0) x (1, 0, 0) in component "REFERENCE thin METAL channel nut side 01R Y"
  circle A0 centre (98, -25) radius 2.6
  dimension "d2741" = 98
  dimension "d2742" = 25
  dimension "d2743" = 5.2
  measures "d2741" horizontal distance of origin A0.centre
  measures "d2742" vertical distance of origin A0.centre
  measures "d2743" diameter of A0
extrude "Thread envelope''''''''''''''''''''" cut sketch "Thread envelope sketch (21)" along normal blind 2.7 bodies 86 in component "REFERENCE thin METAL channel nut side 01R Y"
ref_plane "WorkPlane1" through (0, 0, 17) normal (0, 0, 1) x (1, 0, 0) in component "METAL in-bay corner 11L"
sketch "Vertical bracket leg sketch (7)" plane through (0, 0, 17) normal (0, 0, 1) x (1, 0, 0) in component "METAL in-bay corner 11L"
  line L0 (130, 200) -> (133, 200)
  line L1 (133, 200) -> (133, 218)
  line L2 (133, 218) -> (130, 218)
  line L3 (130, 218) -> (130, 200)
  dimension "d2748" = 130
  dimension "d2749" = 200
  dimension "d2750" = 3
  dimension "d2751" = 18
  constraint horizontal L0
  constraint vertical L1
  constraint horizontal L2
  constraint vertical L3
  measures "d2748" horizontal distance of origin L0.start
  measures "d2749" vertical distance of origin L0.start
  measures "d2750" horizontal distance of L0.start L0.end
  measures "d2751" vertical distance of L0.end L1.end
extrude "Vertical bracket leg''''''" add sketch "Vertical bracket leg sketch (7)" along normal blind 16 separate body makes body 87 in component "METAL in-bay corner 11L"
ref_plane "WorkPlane2" through (0, 0, 17) normal (0, 0, 1) x (1, 0, 0) in component "METAL in-bay corner 11L"
sketch "Horizontal bracket leg sketch (7)" plane through (0, 0, 17) normal (0, 0, 1) x (1, 0, 0) in component "METAL in-bay corner 11L"
  line L0 (130, 215) -> (148, 215)
  line L1 (148, 215) -> (148, 218)
  line L2 (148, 218) -> (130, 218)
  line L3 (130, 218) -> (130, 215)
  dimension "d2756" = 130
  dimension "d2757" = 215
  dimension "d2758" = 18
  dimension "d2759" = 3
  constraint horizontal L0
  constraint vertical L1
  constraint horizontal L2
  constraint vertical L3
  measures "d2756" horizontal distance of origin L0.start
  measures "d2757" vertical distance of origin L0.start
  measures "d2758" horizontal distance of L0.start L0.end
  measures "d2759" vertical distance of L0.end L1.end
extrude "Horizontal bracket leg''''''" add sketch "Horizontal bracket leg sketch (7)" along normal blind 16 bodies 87 in component "METAL in-bay corner 11L"
ref_plane "WorkPlane3" through (130, 0, 0) normal (1, 0, 0) x (0, 1, 0) in component "METAL in-bay corner 11L"
sketch "Vertical rail bolt sketch (7)" plane through (130, 0, 0) normal (1, 0, 0) x (0, 0, -1) in component "METAL in-bay corner 11L"
  circle A0 centre (-25, 206) radius 2.75
  dimension "d2764" = 25
  dimension "d2765" = 206
  dimension "d2766" = 5.5
  measures "d2764" horizontal distance of origin A0.centre
  measures "d2765" vertical distance of origin A0.centre
  measures "d2766" diameter of A0
extrude "Vertical rail bolt''''''" cut sketch "Vertical rail bolt sketch (7)" along normal blind 3 bodies 87 in component "METAL in-bay corner 11L"
ref_plane "WorkPlane4" through (0, 218, 0) normal (0, 1, 0) x (0, 0, 1) in component "METAL in-bay corner 11L"
sketch "Tie bolt sketch (7)" plane through (0, 218, 0) normal (0, 1, 0) x (1, 0, 0) in component "METAL in-bay corner 11L"
  circle A0 centre (142, -25) radius 2.75
  dimension "d2771" = 142
  dimension "d2772" = 25
  dimension "d2773" = 5.5
  measures "d2771" horizontal distance of origin A0.centre
  measures "d2772" vertical distance of origin A0.centre
  measures "d2773" diameter of A0
extrude "Tie bolt''''''" cut sketch "Tie bolt sketch (7)" against normal blind 3 bodies 87 in component "METAL in-bay corner 11L"
ref_plane "WorkPlane1" through (133, 0, 0) normal (1, 0, 0) x (0, 1, 0) in component "REFERENCE side M5x8 11L X"
sketch "Button head envelope sketch (22)" plane through (133, 0, 0) normal (1, 0, 0) x (0, 0, -1) in component "REFERENCE side M5x8 11L X"
  circle A0 centre (-25, 206) radius 4.75
  dimension "d2778" = 25
  dimension "d2779" = 206
  dimension "d2780" = 9.5
  measures "d2778" horizontal distance of origin A0.centre
  measures "d2779" vertical distance of origin A0.centre
  measures "d2780" diameter of A0
extrude "Button head envelope'''''''''''''''''''''" add sketch "Button head envelope sketch (22)" along normal blind 3 separate body makes body 88 in component "REFERENCE side M5x8 11L X"
ref_plane "WorkPlane2" through (133, 0, 0) normal (1, 0, 0) x (0, 1, 0) in component "REFERENCE side M5x8 11L X"
sketch "Shank envelope sketch (22)" plane through (133, 0, 0) normal (1, 0, 0) x (0, 0, -1) in component "REFERENCE side M5x8 11L X"
  circle A0 centre (-25, 206) radius 2.5
  dimension "d2785" = 25
  dimension "d2786" = 206
  dimension "d2787" = 5
  measures "d2785" horizontal distance of origin A0.centre
  measures "d2786" vertical distance of origin A0.centre
  measures "d2787" diameter of A0
extrude "Shank envelope'''''''''''''''''''''" add sketch "Shank envelope sketch (22)" against normal blind 8 bodies 88 in component "REFERENCE side M5x8 11L X"
ref_plane "WorkPlane1" through (0, 0, 20.6) normal (0, 0, 1) x (1, 0, 0) in component "REFERENCE thin METAL channel nut side 11L X"
sketch "Thin nut envelope sketch (22)" plane through (0, 0, 20.6) normal (0, 0, 1) x (1, 0, 0) in component "REFERENCE thin METAL channel nut side 11L X"
  line L0 (125.8, 200) -> (128.5, 200)
  line L1 (128.5, 200) -> (128.5, 212)
  line L2 (128.5, 212) -> (125.8, 212)
  line L3 (125.8, 212) -> (125.8, 200)
  dimension "d2792" = 125.8
  dimension "d2793" = 200
  dimension "d2794" = 2.7
  dimension "d2795" = 12
  constraint horizontal L0
  constraint vertical L1
  constraint horizontal L2
  constraint vertical L3
  measures "d2792" horizontal distance of origin L0.start
  measures "d2793" vertical distance of origin L0.start
  measures "d2794" horizontal distance of L0.start L0.end
  measures "d2795" vertical distance of L0.end L1.end
extrude "Thin nut envelope'''''''''''''''''''''" add sketch "Thin nut envelope sketch (22)" along normal blind 8.8 separate body makes body 89 in component "REFERENCE thin METAL channel nut side 11L X"
ref_plane "WorkPlane2" through (125.8, 0, 0) normal (1, 0, 0) x (0, 1, 0) in component "REFERENCE thin METAL channel nut side 11L X"
sketch "Thread envelope sketch (22)" plane through (125.8, 0, 0) normal (1, 0, 0) x (0, 0, -1) in component "REFERENCE thin METAL channel nut side 11L X"
  circle A0 centre (-25, 206) radius 2.6
  dimension "d2800" = 25
  dimension "d2801" = 206
  dimension "d2802" = 5.2
  measures "d2800" horizontal distance of origin A0.centre
  measures "d2801" vertical distance of origin A0.centre
  measures "d2802" diameter of A0
extrude "Thread envelope'''''''''''''''''''''" cut sketch "Thread envelope sketch (22)" along normal blind 2.7 bodies 89 in component "REFERENCE thin METAL channel nut side 11L X"
ref_plane "WorkPlane1" through (0, 215, 0) normal (0, 1, 0) x (0, 0, 1) in component "REFERENCE side M5x8 11L Y"
sketch "Button head envelope sketch (23)" plane through (0, 215, 0) normal (0, 1, 0) x (1, 0, 0) in component "REFERENCE side M5x8 11L Y"
  circle A0 centre (142, -25) radius 4.75
  dimension "d2807" = 142
  dimension "d2808" = 25
  dimension "d2809" = 9.5
  measures "d2807" horizontal distance of origin A0.centre
  measures "d2808" vertical distance of origin A0.centre
  measures "d2809" diameter of A0
extrude "Button head envelope''''''''''''''''''''''" add sketch "Button head envelope sketch (23)" against normal blind 3 separate body makes body 90 in component "REFERENCE side M5x8 11L Y"
ref_plane "WorkPlane2" through (0, 215, 0) normal (0, 1, 0) x (0, 0, 1) in component "REFERENCE side M5x8 11L Y"
sketch "Shank envelope sketch (23)" plane through (0, 215, 0) normal (0, 1, 0) x (1, 0, 0) in component "REFERENCE side M5x8 11L Y"
  circle A0 centre (142, -25) radius 2.5
  dimension "d2814" = 142
  dimension "d2815" = 25
  dimension "d2816" = 5
  measures "d2814" horizontal distance of origin A0.centre
  measures "d2815" vertical distance of origin A0.centre
  measures "d2816" diameter of A0
extrude "Shank envelope''''''''''''''''''''''" add sketch "Shank envelope sketch (23)" along normal blind 8 bodies 90 in component "REFERENCE side M5x8 11L Y"
ref_plane "WorkPlane1" through (0, 0, 20.6) normal (0, 0, 1) x (1, 0, 0) in component "REFERENCE thin METAL channel nut side 11L Y"
sketch "Thin nut envelope sketch (23)" plane through (0, 0, 20.6) normal (0, 0, 1) x (1, 0, 0) in component "REFERENCE thin METAL channel nut side 11L Y"
  line L0 (136, 219.5) -> (148, 219.5)
  line L1 (148, 219.5) -> (148, 222.2)
  line L2 (148, 222.2) -> (136, 222.2)
  line L3 (136, 222.2) -> (136, 219.5)
  dimension "d2821" = 136
  dimension "d2822" = 219.5
  dimension "d2823" = 12
  dimension "d2824" = 2.7
  constraint horizontal L0
  constraint vertical L1
  constraint horizontal L2
  constraint vertical L3
  measures "d2821" horizontal distance of origin L0.start
  measures "d2822" vertical distance of origin L0.start
  measures "d2823" horizontal distance of L0.start L0.end
  measures "d2824" vertical distance of L0.end L1.end
extrude "Thin nut envelope''''''''''''''''''''''" add sketch "Thin nut envelope sketch (23)" along normal blind 8.8 separate body makes body 91 in component "REFERENCE thin METAL channel nut side 11L Y"
ref_plane "WorkPlane2" through (0, 219.5, 0) normal (0, 1, 0) x (0, 0, 1) in component "REFERENCE thin METAL channel nut side 11L Y"
sketch "Thread envelope sketch (23)" plane through (0, 219.5, 0) normal (0, 1, 0) x (1, 0, 0) in component "REFERENCE thin METAL channel nut side 11L Y"
  circle A0 centre (142, -25) radius 2.6
  dimension "d2829" = 142
  dimension "d2830" = 25
  dimension "d2831" = 5.2
  measures "d2829" horizontal distance of origin A0.centre
  measures "d2830" vertical distance of origin A0.centre
  measures "d2831" diameter of A0
extrude "Thread envelope''''''''''''''''''''''" cut sketch "Thread envelope sketch (23)" along normal blind 2.7 bodies 91 in component "REFERENCE thin METAL channel nut side 11L Y"
ref_plane "WorkPlane1" through (0, 0, 17) normal (0, 0, 1) x (1, 0, 0) in component "METAL in-bay corner 11R"